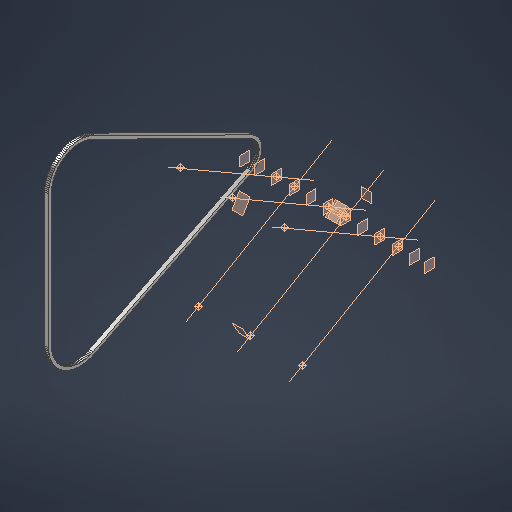
# Autodesk Inventor part: Timing_Chain_Primary_SIMPLIFIED
Saved by Autodesk Inventor 2027.1 (Build 311270010, 270A)
## iProperties
Created: 2026-10-17
Part Number: Timing_Chain_Primary_SIMPLIFIED
Material: Steel, Carbon
Document SubType Name: Modeling
Designer: kashyap
Density: 7.85 g/cm^3
Appearance: Semi-Polished
Material_Status: Assumed for this reconstruction
Author: kashyap
Autodesk Inventor part; units mm, degrees
ref_plane "YZ Plane" through (0, 0, 0) normal (1, 0, 0) x (0, 1, 0)
derived "V6_Engine_Master.ipt"
ref_plane "Bank_A_Plane" through (0, 0, 0) normal (0, 0.8660254, -0.5) x (-1, 0, 0)
ref_plane "Bank_B_Plane" through (0, 0, 0) normal (0, 0.8660254, 0.5) x (-1, 0, 0)
ref_plane "Bank_A_Perp_Plane" through (0, 0, 0) normal (0, 0.5, 0.8660254) x (-1, 0, 0)
ref_plane "Bank_B_Perp_Plane" through (0, 0, 0) normal (0, -0.5, 0.8660254) x (-1, 0, 0)
ref_plane "Bank_A_Deck_Plane" through (0, 112.9, 195.5485) normal (0, 0.5, 0.8660254) x (-1, 0, 0)
ref_plane "Bank_B_Deck_Plane" through (0, -112.9, 195.5485) normal (0, -0.5, 0.8660254) x (-1, 0, 0)
ref_plane "Cyl_A1_Station_Plane" through (-123.8, 0, 0) normal (1, 0, 0) x (0, 1, 0)
ref_plane "Cyl_A2_Station_Plane" through (-18.3, 0, 0) normal (1, 0, 0) x (0, 1, 0)
ref_plane "Cyl_A3_Station_Plane" through (87.2, 0, 0) normal (1, 0, 0) x (0, 1, 0)
ref_plane "Cyl_B1_Station_Plane" through (-87.2, 0, 0) normal (1, 0, 0) x (0, 1, 0)
ref_plane "Cyl_B2_Station_Plane" through (18.3, 0, 0) normal (1, 0, 0) x (0, 1, 0)
ref_plane "Cyl_B3_Station_Plane" through (123.8, 0, 0) normal (1, 0, 0) x (0, 1, 0)
ref_plane "Main_Bearing_Station_1" through (-158.25, 0, 0) normal (1, 0, 0) x (0, 1, 0)
ref_plane "Main_Bearing_Station_2" through (-52.75, 0, 0) normal (1, 0, 0) x (0, 1, 0)
ref_plane "Main_Bearing_Station_3" through (52.75, 0, 0) normal (1, 0, 0) x (0, 1, 0)
ref_plane "Main_Bearing_Station_4" through (158.25, 0, 0) normal (1, 0, 0) x (0, 1, 0)
ref_plane "Front_Interface" through (-188.25, 0, 0) normal (1, 0, 0) x (0, 1, 0)
ref_plane "Rear_Interface" through (188.25, 0, 0) normal (1, 0, 0) x (0, 1, 0)
ref_plane "Oil_Pan_Plane" through (0, 0, -60) normal (0, 0, 1) x (1, 0, 0)
ref_plane "Primary_Sprocket_Plane" through (-193.75, 0, 0) normal (1, 0, 0) x (0, 1, 0)
ref_plane "Secondary_Sprocket_Plane" through (-203.75, 0, 0) normal (1, 0, 0) x (0, 1, 0)
sketch "SK_Chain" plane through (-193.75, 0, 0) normal (1, 0, 0) x (0, 1, 0)
  line L0 (-200.2092, 334.29) -> (-200.1213, 330.933)
  line L1 (-200.1213, 330.933) -> (-199.8578, 327.5851)
  line L2 (-199.8578, 327.5851) -> (-199.4195, 324.2557)
  line L3 (-199.4195, 324.2557) -> (-198.8075, 320.9538)
  line L4 (-198.8075, 320.9538) -> (-198.0236, 317.6884)
  line L5 (-198.0236, 317.6884) -> (-197.0698, 314.4685)
  line L6 (-197.0698, 314.4685) -> (-195.9488, 311.303)
  line L7 (-195.9488, 311.303) -> (-194.6637, 308.2004)
  line L8 (-194.6637, 308.2004) -> (-193.218, 305.1694)
  line L9 (-193.218, 305.1694) -> (-32.9014, -16.7641)
  line L10 (-32.9014, -16.7641) -> (-31.979, -18.4631)
  line L11 (-31.979, -18.4631) -> (-30.9689, -20.1114)
  line L12 (-30.9689, -20.1114) -> (-29.8739, -21.7046)
  line L13 (-29.8739, -21.7046) -> (-28.697, -23.2384)
  line L14 (-28.697, -23.2384) -> (-27.4415, -24.7084)
  line L15 (-27.4415, -24.7084) -> (-26.1107, -26.1107)
  line L16 (-26.1107, -26.1107) -> (-24.7084, -27.4415)
  line L17 (-24.7084, -27.4415) -> (-23.2384, -28.697)
  line L18 (-23.2384, -28.697) -> (-21.7046, -29.8739)
  line L19 (-21.7046, -29.8739) -> (-20.1114, -30.9689)
  line L20 (-20.1114, -30.9689) -> (-18.4631, -31.979)
  line L21 (-18.4631, -31.979) -> (-16.7641, -32.9014)
  line L22 (-16.7641, -32.9014) -> (-15.0192, -33.7337)
  line L23 (-15.0192, -33.7337) -> (-13.2331, -34.4735)
  line L24 (-13.2331, -34.4735) -> (-11.4108, -35.1189)
  line L25 (-11.4108, -35.1189) -> (-9.5572, -35.6679)
  line L26 (-9.5572, -35.6679) -> (-7.6774, -36.1192)
  line L27 (-7.6774, -36.1192) -> (-5.7765, -36.4715)
  line L28 (-5.7765, -36.4715) -> (-3.8598, -36.7239)
  line L29 (-3.8598, -36.7239) -> (-1.9326, -36.8755)
  line L30 (-1.9326, -36.8755) -> (0, -36.9261)
  line L31 (0, -36.9261) -> (1.9326, -36.8755)
  line L32 (1.9326, -36.8755) -> (3.8598, -36.7239)
  line L33 (3.8598, -36.7239) -> (5.7765, -36.4715)
  line L34 (5.7765, -36.4715) -> (7.6774, -36.1192)
  line L35 (7.6774, -36.1192) -> (9.5572, -35.6679)
  line L36 (9.5572, -35.6679) -> (11.4108, -35.1189)
  line L37 (11.4108, -35.1189) -> (13.2331, -34.4735)
  line L38 (13.2331, -34.4735) -> (15.0192, -33.7337)
  line L39 (15.0192, -33.7337) -> (16.7641, -32.9014)
  line L40 (16.7641, -32.9014) -> (18.4631, -31.979)
  line L41 (18.4631, -31.979) -> (20.1114, -30.9689)
  line L42 (20.1114, -30.9689) -> (21.7046, -29.8739)
  line L43 (21.7046, -29.8739) -> (23.2384, -28.697)
  line L44 (23.2384, -28.697) -> (24.7084, -27.4415)
  line L45 (24.7084, -27.4415) -> (26.1107, -26.1107)
  line L46 (26.1107, -26.1107) -> (27.4415, -24.7084)
  line L47 (27.4415, -24.7084) -> (28.697, -23.2384)
  line L48 (28.697, -23.2384) -> (29.8739, -21.7046)
  line L49 (29.8739, -21.7046) -> (30.9689, -20.1114)
  line L50 (30.9689, -20.1114) -> (31.979, -18.4631)
  line L51 (31.979, -18.4631) -> (32.9014, -16.7641)
  line L52 (32.9014, -16.7641) -> (193.218, 305.1694)
  line L53 (193.218, 305.1694) -> (194.6637, 308.2004)
  line L54 (194.6637, 308.2004) -> (195.9488, 311.303)
  line L55 (195.9488, 311.303) -> (197.0698, 314.4685)
  line L56 (197.0698, 314.4685) -> (198.0236, 317.6884)
  line L57 (198.0236, 317.6884) -> (198.8075, 320.9538)
  line L58 (198.8075, 320.9538) -> (199.4195, 324.2557)
  line L59 (199.4195, 324.2557) -> (199.8578, 327.5851)
  line L60 (199.8578, 327.5851) -> (200.1213, 330.933)
  line L61 (200.1213, 330.933) -> (200.2092, 334.29)
  line L62 (200.2092, 334.29) -> (200.1213, 337.647)
  line L63 (200.1213, 337.647) -> (199.8578, 340.9948)
  line L64 (199.8578, 340.9948) -> (199.4195, 344.3242)
  line L65 (199.4195, 344.3242) -> (198.8075, 347.6262)
  line L66 (198.8075, 347.6262) -> (198.0236, 350.8915)
  line L67 (198.0236, 350.8915) -> (197.0698, 354.1114)
  line L68 (197.0698, 354.1114) -> (195.9488, 357.277)
  line L69 (195.9488, 357.277) -> (194.6637, 360.3795)
  line L70 (194.6637, 360.3795) -> (193.218, 363.4105)
  line L71 (193.218, 363.4105) -> (191.6156, 366.3617)
  line L72 (191.6156, 366.3617) -> (189.861, 369.2251)
  line L73 (189.861, 369.2251) -> (187.9589, 371.9926)
  line L74 (187.9589, 371.9926) -> (185.9146, 374.6568)
  line L75 (185.9146, 374.6568) -> (183.7336, 377.2104)
  line L76 (183.7336, 377.2104) -> (181.422, 379.6463)
  line L77 (181.422, 379.6463) -> (178.9861, 381.9579)
  line L78 (178.9861, 381.9579) -> (176.4325, 384.1389)
  line L79 (176.4325, 384.1389) -> (173.7683, 386.1832)
  line L80 (173.7683, 386.1832) -> (171.0007, 388.0853)
  line L81 (171.0007, 388.0853) -> (168.1374, 389.8399)
  line L82 (168.1374, 389.8399) -> (165.1862, 391.4423)
  line L83 (165.1862, 391.4423) -> (162.1552, 392.888)
  line L84 (162.1552, 392.888) -> (159.0527, 394.1731)
  line L85 (159.0527, 394.1731) -> (155.8871, 395.2941)
  line L86 (155.8871, 395.2941) -> (152.6672, 396.2479)
  line L87 (152.6672, 396.2479) -> (149.4019, 397.0318)
  line L88 (149.4019, 397.0318) -> (146.0999, 397.6438)
  line L89 (146.0999, 397.6438) -> (142.7705, 398.0821)
  line L90 (142.7705, 398.0821) -> (139.4227, 398.3456)
  line L91 (139.4227, 398.3456) -> (136.0657, 398.4335)
  line L92 (136.0657, 398.4335) -> (-136.0657, 398.4335)
  line L93 (-136.0657, 398.4335) -> (-139.4227, 398.3456)
  line L94 (-139.4227, 398.3456) -> (-142.7705, 398.0821)
  line L95 (-142.7705, 398.0821) -> (-146.0999, 397.6438)
  line L96 (-146.0999, 397.6438) -> (-149.4019, 397.0318)
  line L97 (-149.4019, 397.0318) -> (-152.6672, 396.2479)
  line L98 (-152.6672, 396.2479) -> (-155.8871, 395.2941)
  line L99 (-155.8871, 395.2941) -> (-159.0527, 394.1731)
  line L100 (-159.0527, 394.1731) -> (-162.1552, 392.888)
  line L101 (-162.1552, 392.888) -> (-165.1862, 391.4423)
  line L102 (-165.1862, 391.4423) -> (-168.1374, 389.8399)
  line L103 (-168.1374, 389.8399) -> (-171.0007, 388.0853)
  line L104 (-171.0007, 388.0853) -> (-173.7683, 386.1832)
  line L105 (-173.7683, 386.1832) -> (-176.4325, 384.1389)
  line L106 (-176.4325, 384.1389) -> (-178.9861, 381.9579)
  line L107 (-178.9861, 381.9579) -> (-181.422, 379.6463)
  line L108 (-181.422, 379.6463) -> (-183.7336, 377.2104)
  line L109 (-183.7336, 377.2104) -> (-185.9146, 374.6568)
  line L110 (-185.9146, 374.6568) -> (-187.9589, 371.9926)
  line L111 (-187.9589, 371.9926) -> (-189.861, 369.2251)
  line L112 (-189.861, 369.2251) -> (-191.6156, 366.3617)
  line L113 (-191.6156, 366.3617) -> (-193.218, 363.4105)
  line L114 (-193.218, 363.4105) -> (-194.6637, 360.3795)
  line L115 (-194.6637, 360.3795) -> (-195.9488, 357.277)
  line L116 (-195.9488, 357.277) -> (-197.0698, 354.1114)
  line L117 (-197.0698, 354.1114) -> (-198.0236, 350.8915)
  line L118 (-198.0236, 350.8915) -> (-198.8075, 347.6262)
  line L119 (-198.8075, 347.6262) -> (-199.4195, 344.3242)
  line L120 (-199.4195, 344.3242) -> (-199.8578, 340.9948)
  line L121 (-199.8578, 340.9948) -> (-200.1213, 337.647)
  line L122 (-200.1213, 337.647) -> (-200.2092, 334.29)
  line L123 (-194.2092, 334.29) -> (-194.1295, 331.247)
  line L124 (-194.1295, 331.247) -> (-193.8907, 328.2123)
  line L125 (-193.8907, 328.2123) -> (-193.4934, 325.1943)
  line L126 (-193.4934, 325.1943) -> (-192.9386, 322.2012)
  line L127 (-192.9386, 322.2012) -> (-192.228, 319.2413)
  line L128 (-192.228, 319.2413) -> (-191.3635, 316.3226)
  line L129 (-191.3635, 316.3226) -> (-190.3474, 313.4532)
  line L130 (-190.3474, 313.4532) -> (-189.1824, 310.6408)
  line L131 (-189.1824, 310.6408) -> (-187.872, 307.8933)
  line L132 (-187.872, 307.8933) -> (-27.5554, -14.0402)
  line L133 (-27.5554, -14.0402) -> (-26.7828, -15.4631)
  line L134 (-26.7828, -15.4631) -> (-25.9368, -16.8436)
  line L135 (-25.9368, -16.8436) -> (-25.0198, -18.1779)
  line L136 (-25.0198, -18.1779) -> (-24.0341, -19.4625)
  line L137 (-24.0341, -19.4625) -> (-22.9826, -20.6936)
  line L138 (-22.9826, -20.6936) -> (-21.8681, -21.8681)
  line L139 (-21.8681, -21.8681) -> (-20.6936, -22.9826)
  line L140 (-20.6936, -22.9826) -> (-19.4625, -24.0341)
  line L141 (-19.4625, -24.0341) -> (-18.1779, -25.0198)
  line L142 (-18.1779, -25.0198) -> (-16.8436, -25.9368)
  line L143 (-16.8436, -25.9368) -> (-15.4631, -26.7828)
  line L144 (-15.4631, -26.7828) -> (-14.0402, -27.5554)
  line L145 (-14.0402, -27.5554) -> (-12.5788, -28.2524)
  line L146 (-12.5788, -28.2524) -> (-11.0829, -28.872)
  line L147 (-11.0829, -28.872) -> (-9.5567, -29.4125)
  line L148 (-9.5567, -29.4125) -> (-8.0043, -29.8724)
  line L149 (-8.0043, -29.8724) -> (-6.4299, -30.2503)
  line L150 (-6.4299, -30.2503) -> (-4.8379, -30.5454)
  line L151 (-4.8379, -30.5454) -> (-3.2327, -30.7567)
  line L152 (-3.2327, -30.7567) -> (-1.6185, -30.8838)
  line L153 (-1.6185, -30.8838) -> (0, -30.9261)
  line L154 (0, -30.9261) -> (1.6185, -30.8838)
  line L155 (1.6185, -30.8838) -> (3.2327, -30.7567)
  line L156 (3.2327, -30.7567) -> (4.8379, -30.5454)
  line L157 (4.8379, -30.5454) -> (6.4299, -30.2503)
  line L158 (6.4299, -30.2503) -> (8.0043, -29.8724)
  line L159 (8.0043, -29.8724) -> (9.5567, -29.4125)
  line L160 (9.5567, -29.4125) -> (11.0829, -28.872)
  line L161 (11.0829, -28.872) -> (12.5788, -28.2524)
  line L162 (12.5788, -28.2524) -> (14.0402, -27.5554)
  line L163 (14.0402, -27.5554) -> (15.4631, -26.7828)
  line L164 (15.4631, -26.7828) -> (16.8436, -25.9368)
  line L165 (16.8436, -25.9368) -> (18.1779, -25.0198)
  line L166 (18.1779, -25.0198) -> (19.4625, -24.0341)
  line L167 (19.4625, -24.0341) -> (20.6936, -22.9826)
  line L168 (20.6936, -22.9826) -> (21.8681, -21.8681)
  line L169 (21.8681, -21.8681) -> (22.9826, -20.6936)
  line L170 (22.9826, -20.6936) -> (24.0341, -19.4625)
  line L171 (24.0341, -19.4625) -> (25.0198, -18.1779)
  line L172 (25.0198, -18.1779) -> (25.9368, -16.8436)
  line L173 (25.9368, -16.8436) -> (26.7828, -15.4631)
  line L174 (26.7828, -15.4631) -> (27.5554, -14.0402)
  line L175 (27.5554, -14.0402) -> (187.872, 307.8933)
  line L176 (187.872, 307.8933) -> (189.1824, 310.6408)
  line L177 (189.1824, 310.6408) -> (190.3474, 313.4532)
  line L178 (190.3474, 313.4532) -> (191.3635, 316.3226)
  line L179 (191.3635, 316.3226) -> (192.228, 319.2413)
  line L180 (192.228, 319.2413) -> (192.9386, 322.2012)
  line L181 (192.9386, 322.2012) -> (193.4934, 325.1943)
  line L182 (193.4934, 325.1943) -> (193.8907, 328.2123)
  line L183 (193.8907, 328.2123) -> (194.1295, 331.247)
  line L184 (194.1295, 331.247) -> (194.2092, 334.29)
  line L185 (194.2092, 334.29) -> (194.1295, 337.333)
  line L186 (194.1295, 337.333) -> (193.8907, 340.3676)
  line L187 (193.8907, 340.3676) -> (193.4934, 343.3856)
  line L188 (193.4934, 343.3856) -> (192.9386, 346.3787)
  line L189 (192.9386, 346.3787) -> (192.228, 349.3386)
  line L190 (192.228, 349.3386) -> (191.3635, 352.2573)
  line L191 (191.3635, 352.2573) -> (190.3474, 355.1268)
  line L192 (190.3474, 355.1268) -> (189.1824, 357.9391)
  line L193 (189.1824, 357.9391) -> (187.872, 360.6866)
  line L194 (187.872, 360.6866) -> (186.4195, 363.3617)
  line L195 (186.4195, 363.3617) -> (184.829, 365.9572)
  line L196 (184.829, 365.9572) -> (183.1048, 368.4659)
  line L197 (183.1048, 368.4659) -> (181.2517, 370.8809)
  line L198 (181.2517, 370.8809) -> (179.2747, 373.1956)
  line L199 (179.2747, 373.1956) -> (177.1794, 375.4037)
  line L200 (177.1794, 375.4037) -> (174.9713, 377.4991)
  line L201 (174.9713, 377.4991) -> (172.6566, 379.476)
  line L202 (172.6566, 379.476) -> (170.2416, 381.3291)
  line L203 (170.2416, 381.3291) -> (167.7329, 383.0533)
  line L204 (167.7329, 383.0533) -> (165.1374, 384.6438)
  line L205 (165.1374, 384.6438) -> (162.4623, 386.0963)
  line L206 (162.4623, 386.0963) -> (159.7148, 387.4068)
  line L207 (159.7148, 387.4068) -> (156.9024, 388.5717)
  line L208 (156.9024, 388.5717) -> (154.033, 389.5878)
  line L209 (154.033, 389.5878) -> (151.1143, 390.4523)
  line L210 (151.1143, 390.4523) -> (148.1544, 391.1629)
  line L211 (148.1544, 391.1629) -> (145.1613, 391.7177)
  line L212 (145.1613, 391.7177) -> (142.1433, 392.115)
  line L213 (142.1433, 392.115) -> (139.1087, 392.3538)
  line L214 (139.1087, 392.3538) -> (136.0657, 392.4335)
  line L215 (136.0657, 392.4335) -> (-136.0657, 392.4335)
  line L216 (-136.0657, 392.4335) -> (-139.1087, 392.3538)
  line L217 (-139.1087, 392.3538) -> (-142.1433, 392.115)
  line L218 (-142.1433, 392.115) -> (-145.1613, 391.7177)
  line L219 (-145.1613, 391.7177) -> (-148.1544, 391.1629)
  line L220 (-148.1544, 391.1629) -> (-151.1143, 390.4523)
  line L221 (-151.1143, 390.4523) -> (-154.033, 389.5878)
  line L222 (-154.033, 389.5878) -> (-156.9024, 388.5717)
  line L223 (-156.9024, 388.5717) -> (-159.7148, 387.4068)
  line L224 (-159.7148, 387.4068) -> (-162.4623, 386.0963)
  line L225 (-162.4623, 386.0963) -> (-165.1374, 384.6438)
  line L226 (-165.1374, 384.6438) -> (-167.7329, 383.0533)
  line L227 (-167.7329, 383.0533) -> (-170.2416, 381.3291)
  line L228 (-170.2416, 381.3291) -> (-172.6566, 379.476)
  line L229 (-172.6566, 379.476) -> (-174.9713, 377.4991)
  line L230 (-174.9713, 377.4991) -> (-177.1794, 375.4037)
  line L231 (-177.1794, 375.4037) -> (-179.2747, 373.1956)
  line L232 (-179.2747, 373.1956) -> (-181.2517, 370.8809)
  line L233 (-181.2517, 370.8809) -> (-183.1048, 368.4659)
  line L234 (-183.1048, 368.4659) -> (-184.829, 365.9572)
  line L235 (-184.829, 365.9572) -> (-186.4195, 363.3617)
  line L236 (-186.4195, 363.3617) -> (-187.872, 360.6866)
  line L237 (-187.872, 360.6866) -> (-189.1824, 357.9391)
  line L238 (-189.1824, 357.9391) -> (-190.3474, 355.1268)
  line L239 (-190.3474, 355.1268) -> (-191.3635, 352.2573)
  line L240 (-191.3635, 352.2573) -> (-192.228, 349.3386)
  line L241 (-192.228, 349.3386) -> (-192.9386, 346.3787)
  line L242 (-192.9386, 346.3787) -> (-193.4934, 343.3856)
  line L243 (-193.4934, 343.3856) -> (-193.8907, 340.3676)
  line L244 (-193.8907, 340.3676) -> (-194.1295, 337.333)
  line L245 (-194.1295, 337.333) -> (-194.2092, 334.29)
  constraints: 492 end point
extrude "Chain_Band_SIMPLIFIED" add sketch "SK_Chain" along normal mid plane 8
body "Solid2"
